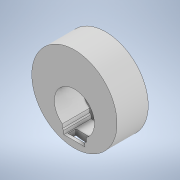
# Autodesk Inventor part: Encaixe-Motor
Saved by Autodesk Inventor 2022 (Build 260153000, 153)
## iProperties
Created: 2022-09-20
Part Number: Encaixe-Motor
Material: Genérico
Document SubType Name: Modeling
Designer: Thierry Nathan
Density: 1 g/cm^3
Appearance: Padrão
Author: Thierry Nathan
Autodesk Inventor part; units mm, degrees
ref_plane "YZ Plane" through (0, 0, 0) normal (1, 0, 0) x (0, 1, 0)
sketch "Esboço1" plane through (0, 0, 0) normal (0, 0, 1) x (1, 0, 0)
  circle A0 centre (0, 0) radius 30
  dimension "d0" = 60
  constraints: 1 centre point, 1 coincident
  measures "d0" diameter of A0
extrude "Extrusão1" add sketch "Esboço1" against normal blind 22
sketch "Esboço2" plane through (0, 0, 0) normal (0, 0, 1) x (1, 0, 0)
  line L0 (0, 0) -> (0, -8)
  circle A0 centre (0, -8) radius 14.125
  dimension "d3" = 8
  dimension "d4" = 28.25
  constraints: 2 end point, 1 centre point, 1 coincident, 1 vertical
  measures "d3" distance of L0.start L0.end
  measures "d4" diameter of A0
extrude "Extrusão2" cut sketch "Esboço2" against normal blind 19.25
sketch "Esboço3" plane through (0, 0, 0) normal (0, 0, 1) x (1, 0, 0)
  circle A0 centre (0, -8) radius 14.125 projected
  line L0 (0, -22.125) -> (0, -25.375)
  line L1 (7.425, -25.375) -> (-7.425, -25.375)
  line L2 (-7.425, -25.375) -> (-7.425, -22.125)
  line L3 (7.425, -22.125) -> (7.425, -25.375)
  line L4 (7.425, -25.375) -> (-7.425, -22.125) construction
  line L5 (-7.425, -25.375) -> (7.425, -22.125) construction
  line L6 (7.425, -22.125) -> (7.425, -20.016)
  line L7 (-7.425, -22.125) -> (-7.425, -20.016)
  point P0 (0, 0)
  point P1 (0, -23.75)
  dimension "d8" = 3.25
  dimension "d9" = 14.85
  constraints: 16 end point, 3 midpoint, 3 point on circle, 2 parallel, 1 horizontal, 1 perpendicular, 1 vertical
  measures "d8" distance of L0.start L0.end
  measures "d9" distance of L1.start L1.end
extrude "Extrusão3" cut sketch "Esboço3" against normal blind 19.25 contours A0 L0 L1 L2 L7 | L6 L3 L1 L0 A0
sketch "Esboço6" plane through (0, 0, 0) normal (0, 0, 1) x (1, 0, 0)
  line L0 (7.425, -25.375) -> (-7.425, -25.375) projected
  line L1 (-7.425, -25.375) -> (-7.425, -22.821)
  line L2 (-7.425, -25.375) -> (-7.425, -20.016) projected
  line L3 (-7.425, -22.821) -> (-8.445, -22.149)
  line L4 (-8.445, -22.149) -> (-8.445, -19.3225)
  arc A0 (7.425, -20.016) -> (-7.425, -20.016) centre (0, -8) ccw projected
  line L5 (7.425, -20.016) -> (7.425, -25.375) projected
  line L6 (7.425, -22.821) -> (8.425, -22.149)
  line L7 (8.425, -22.149) -> (8.425, -19.3373)
  point P0 (0, 0)
  dimension "d18" = 2.554
  constraints: 10 end point, 2 point on circle, 2 point on line, 2 vertical
  measures "d18" distance of L0.end L1.end
extrude "Extrusão5" cut sketch "Esboço6" against normal blind 19.25 contours L5 A0 L7 L6 | L3 L4 A0 L2
ref_plane "Plano de trabalho5" through (-30, 0, 0) normal (-1, 0, 0) x (0, -1, 0)
sketch "Esboço9" plane through (-30, 0, 0) normal (-1, 0, 0) x (0, -1, 0)
  line L0 (0, 0) -> (0, -11)
  line L1 (10.1, -9.4) -> (-10.1, -9.4)
  line L2 (-10.1, -9.4) -> (-10.1, -12.6)
  line L3 (-10.1, -12.6) -> (10.1, -12.6)
  line L4 (10.1, -12.6) -> (10.1, -9.4)
  line L5 (10.1, -9.4) -> (-10.1, -12.6) construction
  line L6 (-10.1, -9.4) -> (10.1, -12.6) construction
  dimension "d27" = 11
  dimension "d28" = 3.2
  dimension "d29" = 20.2
  constraints: 14 end point, 2 midpoint, 2 parallel, 1 horizontal, 1 perpendicular, 1 vertical
  measures "d27" distance of L0.start L0.end
  measures "d28" distance of L1.end L2.end
  measures "d29" distance of L2.end L3.end
extrude "Extrusão6" cut sketch "Esboço9" against normal blind 10
ref_plane "Plano de trabalho6" through (0, -30, 0) normal (0, 1, 0) x (1, 0, 0)
sketch "Esboço11" plane through (0, -30, 0) normal (0, 1, 0) x (1, 0, 0)
  line L0 (0, 0) -> (0, 2.2)
  line L1 (0, 2.2) -> (0, 4.95)
  line L2 (6.59, 7.7) -> (-6.59, 7.7)
  line L3 (-6.59, 7.7) -> (-6.59, 2.2)
  line L4 (-6.59, 2.2) -> (6.59, 2.2)
  line L5 (6.59, 2.2) -> (6.59, 7.7)
  line L6 (6.59, 7.7) -> (-6.59, 2.2) construction
  line L7 (-6.59, 7.7) -> (6.59, 2.2) construction
  dimension "d32" = 2.2
  dimension "d33" = 2.75
  dimension "d34" = 13.18
  constraints: 16 end point, 2 midpoint, 2 parallel, 2 vertical, 1 horizontal, 1 perpendicular
  measures "d32" distance of L0.start L0.end
  measures "d33" distance of L0.end L1.end
  measures "d34" distance of L2.start L2.end
extrude "Extrusão7" cut sketch "Esboço11" along normal blind 10
